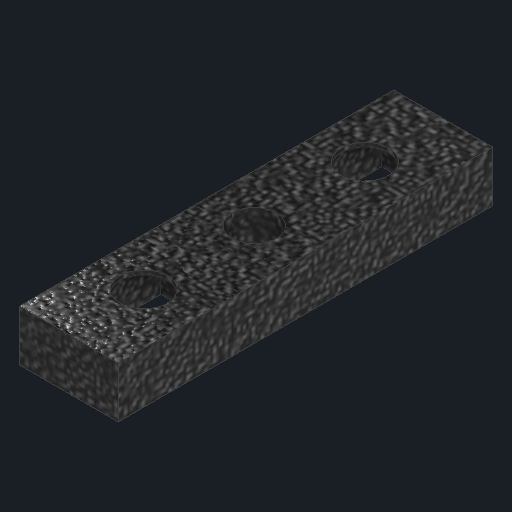
# Autodesk Inventor part: ra_worm_carrier
Saved by Autodesk Inventor 2027.1 (Build 311270010, 270A)
## iProperties
Created: 2026-11-04
Part Number: ra_worm_carrier
Material: Generic
Description: RA worm carrier strip: 2x M5 cap screws + M5 push grub (worm mesh adjust), from photos
Document SubType Name: Modeling
Designer: Claude (from photos)
Density: 1 g/cm^3
Appearance: Black Cast
Author: alexg
Autodesk Inventor part; units mm, degrees
ref_plane "Work Plane1" through (0, -54, 0) normal (0, 1, 0) x (-1, 0, 0)
sketch "Carrier strip sketch" plane through (0, -54, 0) normal (0, 1, 0) x (-1, 0, 0)
  line L0 (-33.4, -22) -> (-45, -22)
  line L1 (-45, -22) -> (-45, 22)
  line L2 (-45, 22) -> (-33.4, 22)
  line L3 (-33.4, 22) -> (-33.4, -22)
  constraints: 8 end point, 2 parallel, 1 horizontal, 1 perpendicular
extrude "Carrier strip" add sketch "Carrier strip sketch" along normal blind 6
ref_plane "Work Plane2" through (0, -54, 0) normal (0, 1, 0) x (-1, 0, 0)
sketch "Bolt head counterbores sketch" plane through (0, -54, 0) normal (0, 1, 0) x (-1, 0, 0)
  line L0 (-34.5, 6.5) -> (-43.5, 6.5)
  line L1 (-43.5, 6.5) -> (-43.5, 19.5)
  line L2 (-43.5, 19.5) -> (-34.5, 19.5)
  line L3 (-34.5, 19.5) -> (-34.5, 6.5)
  line L4 (-34.5, -19.5) -> (-43.5, -19.5)
  line L5 (-43.5, -19.5) -> (-43.5, -6.5)
  line L6 (-43.5, -6.5) -> (-34.5, -6.5)
  line L7 (-34.5, -6.5) -> (-34.5, -19.5)
  constraints: 16 end point, 4 parallel, 2 horizontal, 2 perpendicular
extrude "Bolt head counterbores" cut sketch "Bolt head counterbores sketch" along normal blind 5.5
ref_plane "Work Plane3" through (0, -54, 0) normal (0, 1, 0) x (-1, 0, 0)
sketch "Grub pocket sketch" plane through (0, -54, 0) normal (0, 1, 0) x (-1, 0, 0)
  line L0 (-35.5, -3.5) -> (-42.5, -3.5)
  line L1 (-42.5, -3.5) -> (-42.5, 3.5)
  line L2 (-42.5, 3.5) -> (-35.5, 3.5)
  line L3 (-35.5, 3.5) -> (-35.5, -3.5)
  constraints: 8 end point, 2 parallel, 1 horizontal, 1 perpendicular
extrude "Grub pocket" cut sketch "Grub pocket sketch" along normal blind 2
ref_plane "Work Plane4" through (0, -54, 0) normal (0, 1, 0) x (-1, 0, 0)
sketch "Bolt clearance + grub holes sketch" plane through (0, -54, 0) normal (0, 1, 0) x (-1, 0, 0)
  circle A0 centre (-39, 13) radius 2.8
  circle A1 centre (-39, -13) radius 2.8
  circle A2 centre (-39, 0) radius 2.6
  constraints: 3 centre point
extrude "Bolt clearance + grub holes" cut sketch "Bolt clearance + grub holes sketch" along normal blind 6
body "Solid1"
